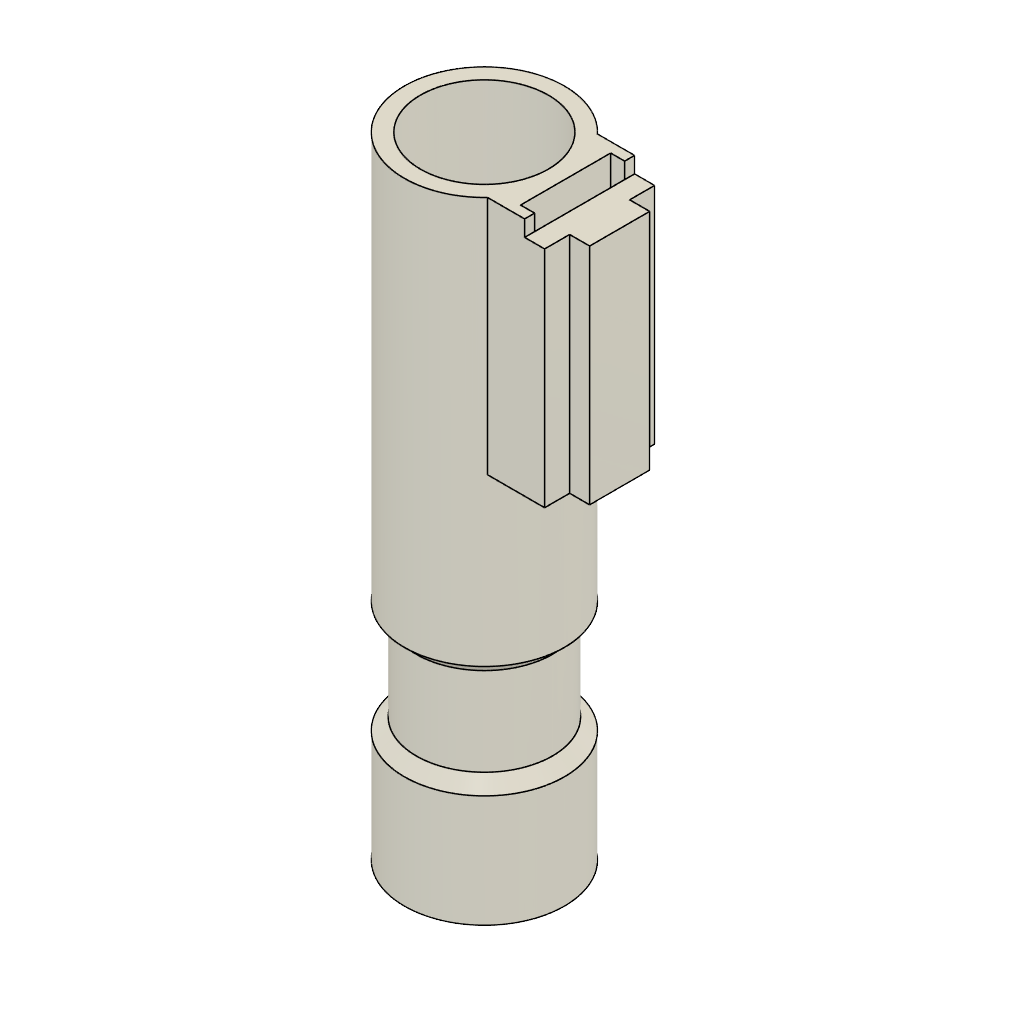
RealMainAssembly (Autodesk Fusion 360 archive; units mm, degrees)
design "upper_shaft"
part number: 2026-10-18-16-02-19-659
Autodesk Fusion 360 part; units mm, degrees
sketch "Sketch1" plane through (0, 0, 0) normal (0, 1, 0) x (1, 0, 0)
  circle A0 centre (0, 0) radius 4
  dimension "d1" = 8
  constraint coincident A0.centre origin
  measures "d1" diameter of A0
extrude "Extrude1" add sketch "Sketch1" along normal blind 5.9
sketch "Sketch2" plane through (0, 5.9, 0) normal (0, 1, 0) x (-1, 0, 0)
  circle A0 centre (0, 0) radius 4
  circle A1 centre (0, 0) radius 3.4
  dimension "d4" = 6.8
  constraint coincident A0.centre A1.centre
  measures "d4" diameter of A1
extrude "Extrude2" add sketch "Sketch2" along normal blind 5 contours A1
sketch "Sketch3" plane through (0, 10.9, 0) normal (0, 1, 0) x (-1, 0, 0)
  circle A0 centre (0, 0) radius 3.4
  circle A1 centre (0, 0) radius 4
  dimension "d7" = 8
  constraint coincident A0.centre A1.centre
  measures "d7" diameter of A1
extrude "Extrude3" add sketch "Sketch3" along normal blind 20.6 contours A0 | A1
chamfer "Chamfer1" distance 0.3 angle 45 2 edges at (3.1699, 5.9, 1.2295) (-3.7293, 5.9, 1.4465) tangent chain off
chamfer "Chamfer2" distance 0.3 angle 45 2 edges at (3.1699, 10.9, -1.2295) (3.7293, 10.9, -1.4465) tangent chain off
hole "Hole1" at (0, 31.5, 0) direction (0, -1, 0) diameter 6.4 end through all
sketch "Sketch4" plane through (0, 31.5, 0) normal (0, 1, 0) x (-1, 0, 0)
  circle A0 centre (0, 0) radius 3.2
  circle A1 centre (0, 0) radius 4
  line L0 (-2.9047, -2.75) -> (-6.76, -2.75)
  line L1 (-2.9047, 2.75) -> (-6.76, 2.75)
  line L2 (-6.76, -2.75) -> (-6.76, 2.75)
  dimension "d16" = 6.76
  dimension "d17" = 5.5
  constraint coincident A1 L0.start
  constraint horizontal L0
  constraint coincident A1 L1.start
  constraint horizontal L1
  constraint equal L0 L1
  measures "d16" horizontal distance of A0.centre L0.end
  measures "d17" distance of L0.start L1.start
extrude "Extrude4" add sketch "Sketch4" against normal blind 12 contours A1 L0 L1 L2
sketch "Sketch5" plane through (0, 31.5, 0) normal (0, 1, 0) x (-1, 0, 0)
  circle A0 centre (0, 0) radius 3.2
  arc A1 (-2.9047, -2.75) -> (-2.9047, 2.75) centre (0, 0) ccw
  line L0 (-2.9047, 2.75) -> (-6.76, 2.75)
  line L1 (-6.76, 2.75) -> (-6.76, -2.75)
  line L2 (-6.76, -2.75) -> (-2.9047, -2.75)
  line L3 (0, 0) -> (-6.76, 0) construction
  line L4 (-4.06, 0) -> (-4.06, -2.25)
  line L5 (-4.06, 0) -> (-4.06, 2.25)
  line L6 (-4.06, -2.25) -> (-4.76, -2.25)
  line L7 (-4.76, -2.25) -> (-4.76, 2.25)
  line L8 (-4.76, 2.25) -> (-4.06, 2.25)
  dimension "d30" = 2.25
  dimension "d31" = 2.25
  dimension "d32" = 0.7
  dimension "d33" = 4.5
  dimension "d34" = 4.06
  constraint coincident A0.centre A1.centre
  constraint midpoint L1 L3.end
  constraint coincident L3 L4.start
  constraint perpendicular L3 L4
  constraint perpendicular L3 L5
  constraint perpendicular L4 L6
  constraint perpendicular L6 L7
  measures "d30" distance of L4.start L4.end
  measures "d31" distance of L4.start L5.end
  measures "d32" distance of L4.end L6.end
  measures "d33" distance of L6.end L7.end
  measures "d34" distance of A0.centre L4
extrude "Extrude5" cut sketch "Sketch5" against normal blind 9 contours L4 L5 L6 L7 L8
sketch "Sketch6" plane through (0, 31.5, 0) normal (0, 1, 0) x (-1, 0, 0)
  line L0 (-4.76, 2.25) -> (-4.06, 2.25)
  line L1 (-4.06, 2.25) -> (-4.06, -2.25)
  line L2 (-4.06, -2.25) -> (-4.76, -2.25)
  line L3 (-4.76, -2.25) -> (-4.76, 2.25)
  circle A0 centre (0, 0) radius 3.2
  arc A1 (-2.9047, -2.75) -> (-2.9047, 2.75) centre (0, 0) ccw
  line L4 (-2.9047, 2.75) -> (-6.76, 2.75)
  line L5 (-6.76, 2.75) -> (-6.76, -2.75)
  line L6 (-6.76, -2.75) -> (-2.9047, -2.75)
  line L7 (-6.76, -2.75) -> (-5.76, -2.75)
  line L8 (-5.76, -2.75) -> (-5.76, -1.5)
  line L9 (-5.76, -1.5) -> (-6.76, -1.5)
  line L10 (-6.76, -1.5) -> (-6.76, -2.75)
  line L11 (-6.76, 2.75) -> (-5.76, 2.75)
  line L12 (-5.76, 2.75) -> (-5.76, 1.5)
  line L13 (-5.76, 1.5) -> (-6.76, 1.5)
  line L14 (-6.76, 1.5) -> (-6.76, 2.75)
  dimension "d37" = 3
  dimension "d39" = 5.76
  constraint horizontal L7
  constraint vertical L8
  constraint horizontal L9
  constraint vertical L10
  constraint coincident L5.end L6.start
  constraint horizontal L11
  constraint vertical L12
  constraint horizontal L13
  constraint vertical L14
  constraint coincident L4.end L5.start
  constraint equal L9 L13
  constraint equal L8 L12
  measures "d37" distance of L9.end L13.end
  measures "d39" distance of A0.centre L8
extrude "Extrude6" cut sketch "Sketch6" against normal blind 12 contours L5 L6 L7 L8 L9 L10 | L4 L5 L11 L12 L13 L14
sketch "Sketch7" plane through (6.76, 0, 0) normal (1, 0, 0) x (0, 0, -1)
  line L0 (-1.5, 31.5) -> (-1.5, 19.5)
  line L1 (-1.5, 19.5) -> (1.5, 19.5)
  line L2 (1.5, 19.5) -> (1.5, 31.5)
  line L3 (1.5, 31.5) -> (-1.5, 31.5)
  line L4 (-1.5, 31.5) -> (12.2094, 31.5)
  line L5 (12.2094, 31.5) -> (12.2094, 30.7)
  line L6 (12.2094, 30.7) -> (-1.5, 30.7)
  line L7 (-1.5, 30.7) -> (-1.5, 31.5)
  dimension "d42" = 0.8
  constraint horizontal L4
  constraint vertical L5
  constraint horizontal L6
  constraint vertical L7
  constraint coincident L0.start L3.end
  measures "d42" distance of L0.start L6.end
extrude "Extrude7" cut sketch "Sketch7" against normal blind 2 contours L2 L4 L5 L6
sketch "Sketch9" plane through (5.76, 0, 0) normal (1, 0, 0) x (0, 0, -1)
  line L0 (-1.5, 31.5) -> (-2.75, 31.5)
  line L1 (-2.75, 31.5) -> (-2.75, 19.5)
  line L2 (-2.75, 19.5) -> (-1.5, 19.5)
  line L3 (-1.5, 19.5) -> (-1.5, 31.5)
  line L4 (-2.75, 31.5) -> (-1.5, 31.5)
  line L5 (-1.5, 31.5) -> (-1.5, 30.7)
  line L6 (-1.5, 30.7) -> (-2.75, 30.7)
  line L7 (-2.75, 30.7) -> (-2.75, 31.5)
  dimension "d49" = 0.8
  constraint horizontal L4
  constraint vertical L5
  constraint horizontal L6
  constraint vertical L7
  constraint coincident L0.end L1.start
  measures "d49" distance of L0.end L6.end
extrude "Extrude9" cut sketch "Sketch9" against normal blind 1 contours L0 L1 L3 L4 L5 L6 L7
sketch "Sketch10" plane through (6.76, 0, 0) normal (1, 0, 0) x (0, 0, -1)
  line L0 (-1.5, 31.5) -> (-1.5, 19.5)
  line L1 (-1.5, 19.5) -> (1.5, 19.5)
  line L2 (1.5, 19.5) -> (1.5, 31.5)
  line L3 (1.5, 31.5) -> (-1.5, 31.5)
  line L4 (-1.5, 31.5) -> (1.5, 31.5)
  line L5 (1.5, 31.5) -> (1.5, 30.7)
  line L6 (1.5, 30.7) -> (-1.5, 30.7)
  line L7 (-1.5, 30.7) -> (-1.5, 31.5)
  dimension "d52" = 0.8
  constraint horizontal L4
  constraint vertical L5
  constraint horizontal L6
  constraint vertical L7
  constraint coincident L0.start L3.end
  measures "d52" distance of L0.start L6.end
extrude "Extrude10" cut sketch "Sketch10" against normal blind 2 contours L0 L2 L3 L4 L5 L6 L7
scale "Scale2" factor 3 about (4.76, 30.7, -2.75) bodies 1
equation "d5 = ( 45.9 mm - 5.9 mm ) - 35 mm"
equation "d8 = 66.50 mm - 45.9 mm"
equation "d30 = ( 4.5 / 2 ) * 1 mm"
equation "d31 = ( 4.5 / 2 ) * 1 mm"

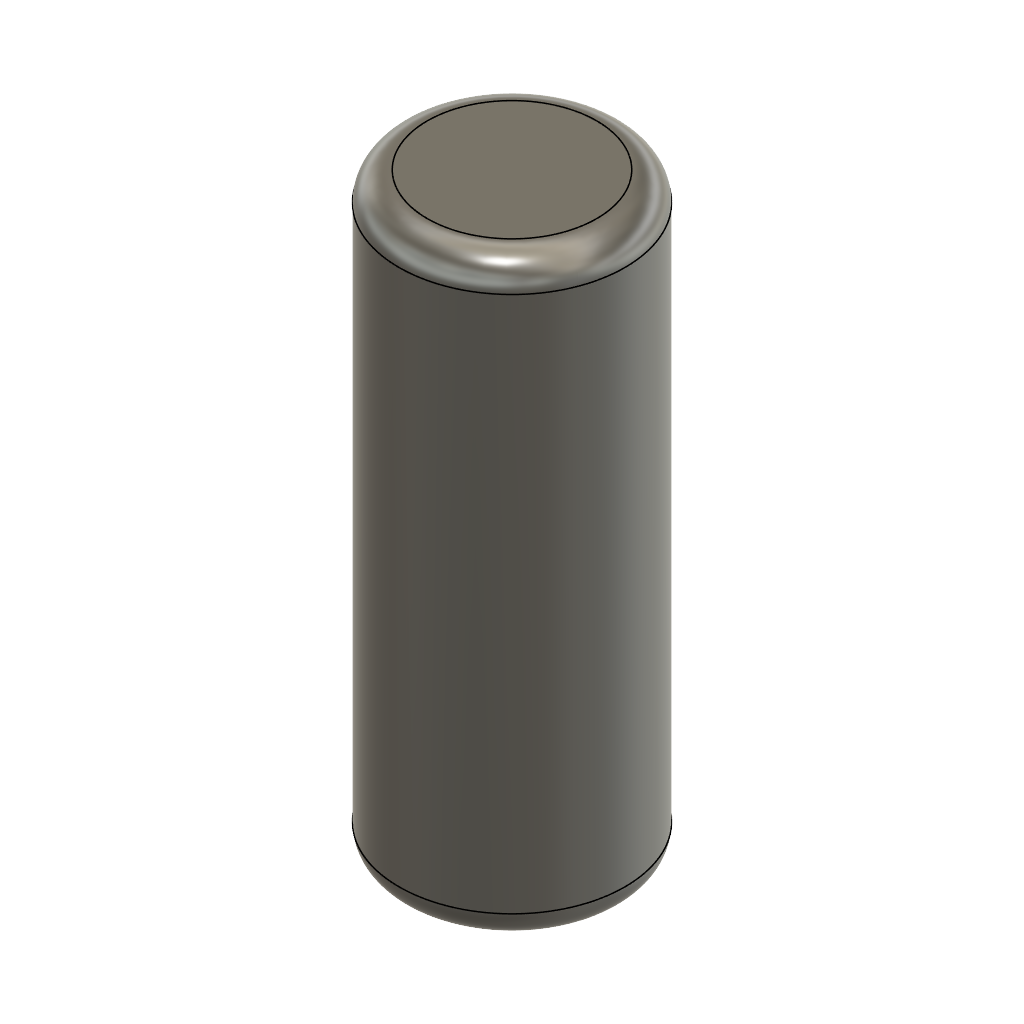
design "ERASER"
part number: 2026-10-18-16-44-17-259
Autodesk Fusion 360 part; units mm, degrees
sketch "Sketch1" plane through (0, 0, 0) normal (0, 1, 0) x (1, 0, 0)
  circle A0 centre (0, 0) radius 2
  dimension "d1" = 4
  constraint coincident A0.centre origin
  measures "d1" diameter of A0
extrude "Extrude1" add sketch "Sketch1" along normal blind 10.5
fillet "Fillet1" radius 0.5 2 edges at (-1.8647, 10.5, 0.7232) (-1.8647, 0, 0.7232)
scale "Scale1" factor 3 about (-2, 10, 0) bodies 1

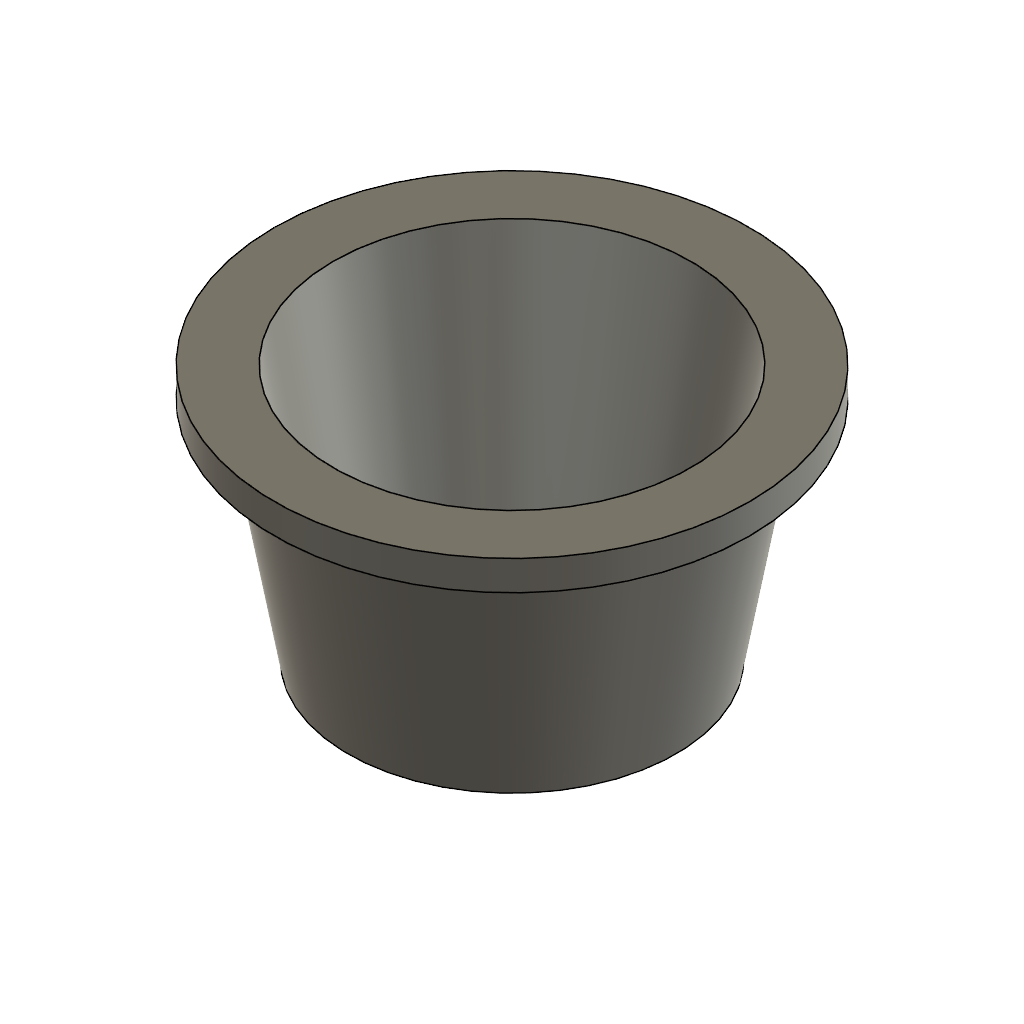
design "dispenser_ring"
part number: 2026-10-18-07-58-24-911
Autodesk Fusion 360 part; units mm, degrees
sketch "Sketch2" plane through (0, 0, 0) normal (0, 1, 0) x (1, 0, 0)
  circle A0 centre (0, 0) radius 1.38
  dimension "d10" = 2.76
  constraint coincident A0.centre origin
  measures "d10" diameter of A0
extrude "Extrude1" add sketch "Sketch2" along normal blind 1.9 draft 10
sketch "Sketch3" plane through (0, 1.9, 0) normal (0, 1, 0) x (-1, 0, 0)
  circle A0 centre (0, 0) radius 1.715
  circle A1 centre (0, 0) radius 2
  dimension "d13" = 4
  constraint coincident A0.centre A1.centre
  measures "d13" diameter of A1
extrude "Extrude2" add sketch "Sketch3" along normal blind 0.25 contours A0 | A1
shell "Shell1" thickness 0.25 removed faces 1 at (-0.637, 2.15, 0.1965)
sketch "Sketch4" plane through (0, 0.25, 0) normal (0, 1, 0) x (-1, 0, 0)
  circle A0 centre (0, 0) radius 1.1702
  circle A1 centre (0, 0) radius 0.95
  dimension "d17" = 1.9
  constraint coincident A0.centre A1.centre
  measures "d17" diameter of A1
sketch "Sketch5" plane through (0, 0, 0) normal (0, -1, 0) x (1, 0, 0)
  circle A0 centre (0, 0) radius 1.38
  circle A1 centre (0, 0) radius 0.8
  dimension "d18" = 1.6
  constraint coincident A0.centre A1.centre
  measures "d18" diameter of A1
loft "Loft1" cut profiles "Sketch4", "Sketch5" section 1 contours A1 section 2 contours A1
scale "Scale1" factor 3 about (2, 1.9, 0) bodies 1

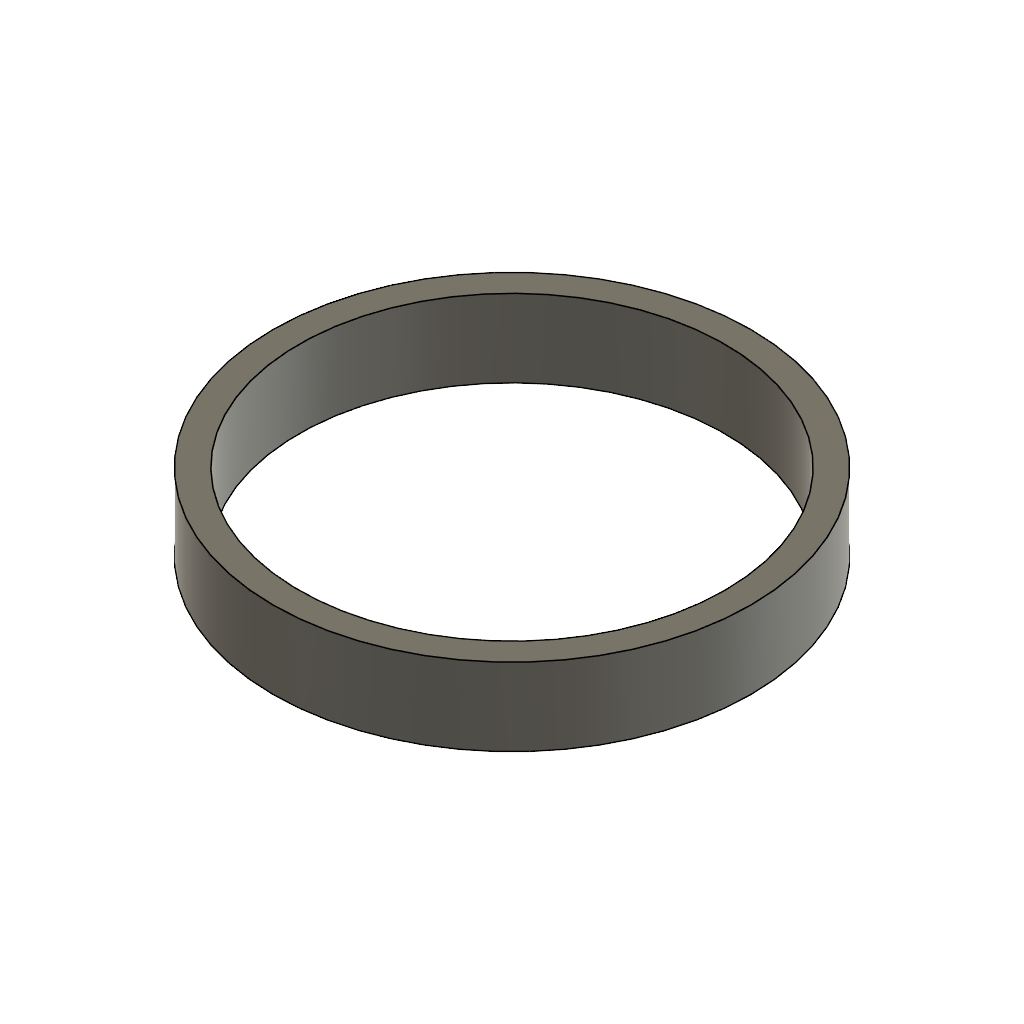
design "RING1"
part number: 2026-10-18-00-34-46-271
Autodesk Fusion 360 part; units mm, degrees
sketch "Sketch1" plane through (0, 0, 0) normal (0, 1, 0) x (1, 0, 0)
  circle A0 centre (0, 0) radius 4.2
  dimension "d1" = 8.4
  constraint coincident A0.centre origin
  measures "d1" diameter of A0
extrude "Extrude1" add sketch "Sketch1" along normal blind 1.5
sketch "Sketch2" plane through (0, 1.5, 0) normal (0, 1, 0) x (-1, 0, 0)
  circle A0 centre (0, 0) radius 4.2
  circle A1 centre (0, 0) radius 4.12
  dimension "d4" = 0.08
  constraint coincident A0.centre A1.centre
  measures "d4" distance of A0 A1
extrude "Extrude2" cut sketch "Sketch2" against normal blind 1.8 contours A1
scale "Scale1" factor 3 about (-4.2, 0, 0) bodies 1
move_face "OffsetFaces1" offset 1.26 1 faces at (20.9843, 3, 0.6281)

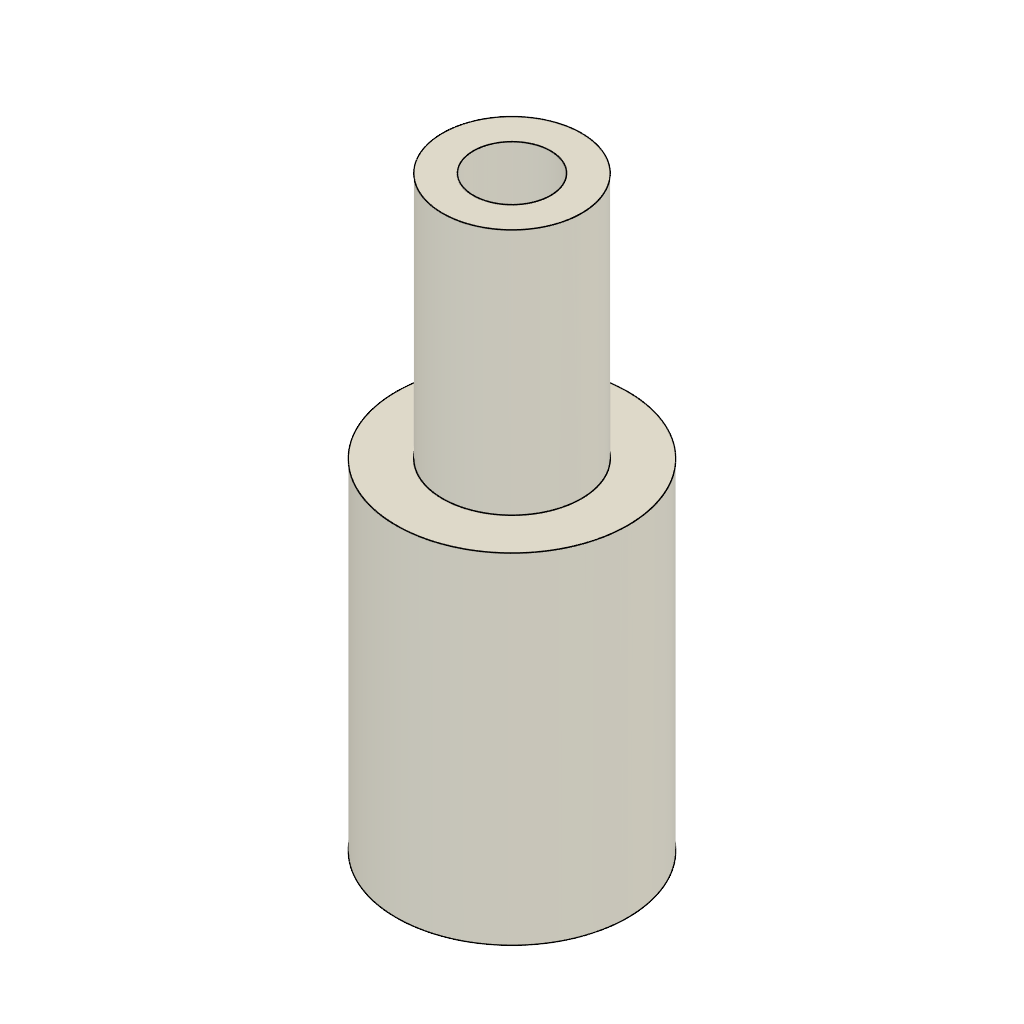
design "Coupling_1"
part number: 2026-10-18-00-37-06-966
Autodesk Fusion 360 part; units mm, degrees
sketch "Sketch1" plane through (0, 0, 0) normal (0, 0, 1) x (1, 0, 0)
  line L0 (0, 0) -> (1.5, 0)
  line L1 (1.5, 0) -> (1.5, 4.4)
  line L2 (1.5, 4.4) -> (0, 4.4)
  line L3 (0, 4.4) -> (0, 0)
  line L4 (0, 4.4) -> (0.9, 4.4)
  line L5 (0.9, 4.4) -> (0.9, 7.6)
  line L6 (0.9, 7.6) -> (0, 7.6)
  line L7 (0, 7.6) -> (0, 4.4)
  line L8 (0, 0) -> (0.65, 0)
  line L9 (0.65, 0) -> (0.65, 1.75)
  line L10 (0.65, 1.75) -> (0, 1.75)
  line L11 (0, 1.75) -> (0, 0)
  dimension "d1" = 1.5
  dimension "d2" = 4.4
  dimension "d3" = 0.9
  dimension "d4" = 7.6
  dimension "d5" = 0.65
  dimension "d6" = 1.75
  constraint horizontal L0
  constraint vertical L1
  constraint horizontal L2
  constraint vertical L3
  constraint coincident L0.start L3.end
  constraint horizontal L4
  constraint vertical L5
  constraint horizontal L6
  constraint vertical L7
  constraint horizontal L8
  constraint vertical L9
  constraint horizontal L10
  constraint vertical L11
  measures "d1" distance of L0.start L0.end
  measures "d2" distance of L0.start L2.end
  measures "d3" distance of L2.end L4.end
  measures "d4" distance of L0.start L6.end
  measures "d5" distance of L0.start L8.end
  measures "d6" distance of L0.start L10.end
revolve "Revolve1" add sketch "Sketch1" angle 360 about axis through (0, 1.75, 0) along (0, -1, 0) contours L0 L1 L2 L3 L4 L9 L10 | L2 L4 L5 L6 L7
sketch "Sketch2" plane through (0, 7.6, 0) normal (0, 1, 0) x (-1, 0, 0)
  circle A0 centre (0, 0) radius 0.9
  circle A1 centre (0, 0) radius 0.5
  dimension "d8" = 1
  constraint coincident A0.centre A1.centre
  measures "d8" diameter of A1
extrude "Extrude1" cut sketch "Sketch2" against normal blind 5.85 contours A1
scale "Scale1" factor 3 about (0.9, 4.4, 0) bodies 1
equation "d1 = ( 3 / 2 ) * 1 mm"
equation "d3 = ( 1.8 / 2 ) * 1 mm"
equation "d5 = ( 1.3 / 2 ) * 1 mm"

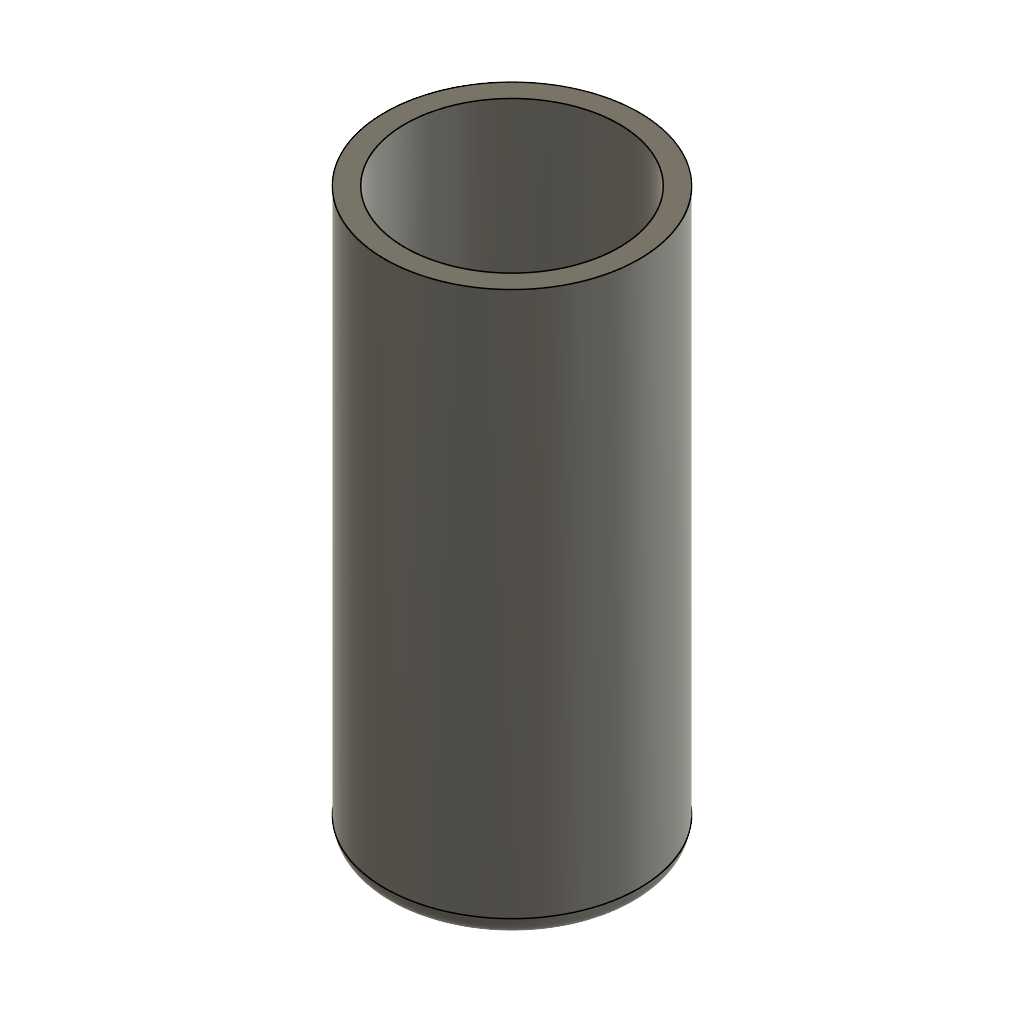
design "Eraser_cap"
part number: 2026-10-18-16-46-40-232
Autodesk Fusion 360 part; units mm, degrees
sketch "Sketch1" plane through (0, 0, 0) normal (0, 1, 0) x (1, 0, 0)
  circle A0 centre (0, 0) radius 3.15
  dimension "d1" = 6.3
  constraint coincident A0.centre origin
  measures "d1" diameter of A0
extrude "Extrude1" add sketch "Sketch1" along normal blind 14
hole "Hole1" at (0, 14, 0) direction (0, -1, 0) diameter 5.3 depth 13 tip angle 180
fillet "Fillet1" radius 0.5 1 edges at (-2.9368, 0, 1.1391)
scale "Scale1" factor 3 about (0, 1, 2.65) bodies 1

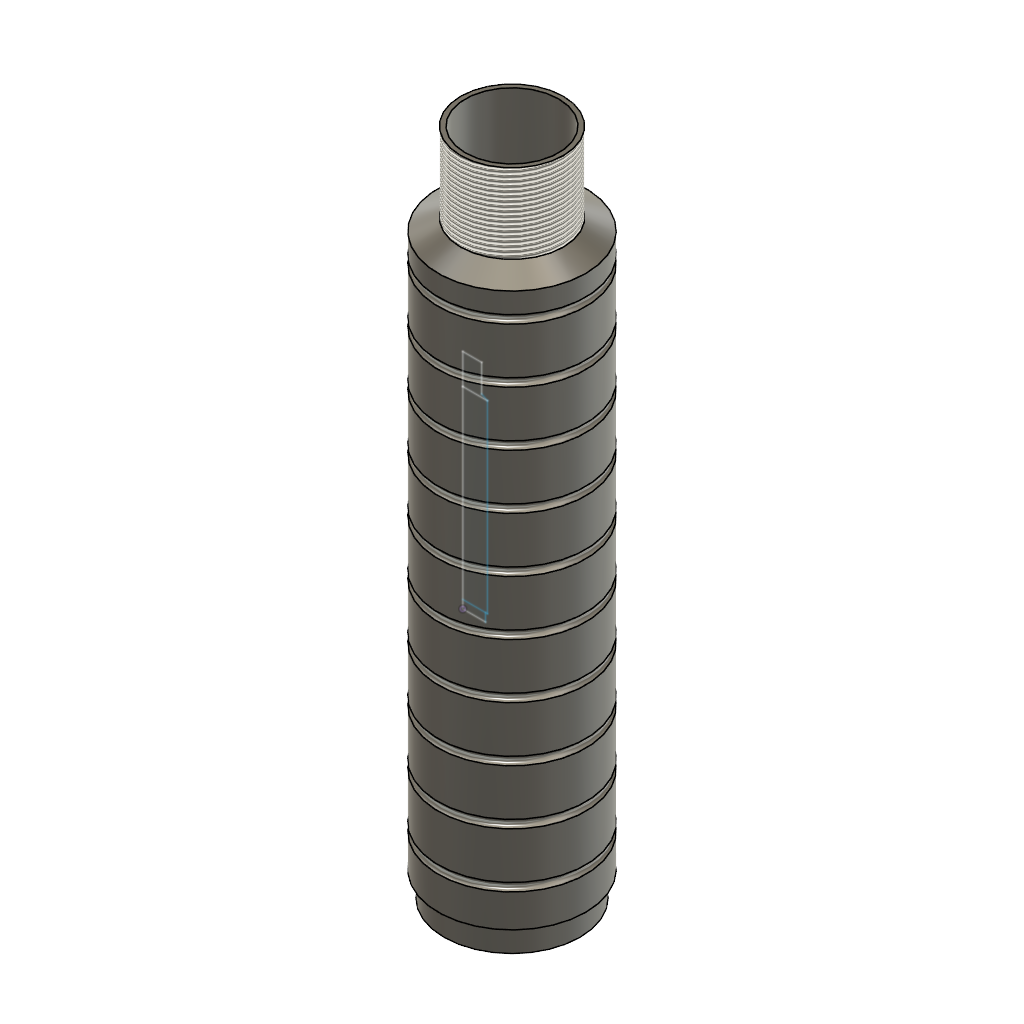
design "GRIP"
part number: 2026-10-18-08-55-25-582
Autodesk Fusion 360 part; units mm, degrees
sketch "Sketch4" plane through (0, 0, 0) normal (0, 0, 1) x (1, 0, 0)
  line L0 (0, 0) -> (4.15, 0)
  line L1 (4.5, 1.5) -> (4.5, 35.25)
  line L2 (4.5, 35.25) -> (0, 35.25)
  line L3 (0, 35.25) -> (0, 0)
  line L4 (0, 40.8) -> (3.45, 40.8)
  line L5 (3.45, 40.8) -> (3.45, 35.8)
  line L6 (3.45, 35.8) -> (4.5, 35.25)
  line L7 (0, 40.8) -> (0, 35.25)
  line L8 (4.5, 1.5) -> (0, 1.5)
  line L9 (4.15, 1.5) -> (4.15, 0)
  dimension "d10" = 35.25
  dimension "d12" = 3.45
  dimension "d13" = 0.55
  dimension "d39" = 0.35
  dimension "d41" = 40.8
  constraint horizontal L0
  constraint vertical L1
  constraint horizontal L2
  constraint vertical L3
  constraint coincident L0.start L3.end
  constraint horizontal L4
  constraint perpendicular L4 L5
  constraint perpendicular L2 L7
  constraint coincident L3 L8.end
  constraint perpendicular L3 L8
  constraint coincident L8 L9.start
  constraint perpendicular L0 L9
  measures "d10" distance of L0.start L2.end
  measures "d12" distance of L4.start L4.end
  measures "d13" vertical distance of L1.end L5.end
  measures "d39" distance of L1.start L9.start
  measures "d41" distance of L0.start L4.start
revolve "Revolve1" add sketch "Sketch4" angle 360 about axis through (0, 35.25, 0) along (0, -1, 0)
hole "Hole2" at (0, 40.8, 0) direction (0, -1, 0) diameter 5.7 end through all
sketch "Sketch6" plane through (0, 0, 0) normal (0, 0, 1) x (1, 0, 0)
  circle A0 centre (4.5, 33.75) radius 0.25
  point P0 (4.5, 35.25)
  dimension "d30" = 0.5
  dimension "d36" = 1.5
  measures "d30" diameter of A0
  measures "d36" distance of A0.centre P0
revolve "Revolve2" cut sketch "Sketch6" angle 360 about axis through (0, 1.5, 0) along (0, 1, 0)
pattern_linear "R-Pattern1" count 10 spacing 3.333 along (0, -1, 0) of 1 faces at (4.482, 33.9997, 0.2237)
thread "Thread2" "ANSI Unified Screw Threads 0.25 1/4-32 UNEF 1/4-32 UNEF 3A" major diameter 6.2738 minor diameter 5.4051 pitch 0.7937 angle 60 resizes the face on face at (3.4457, 39.1333, -0.172)
scale "Scale1" factor 3 about (-4.5, 20.668, 0) bodies 1
equation "d12 = ( 6.9 / 2 ) * 1 mm"
equation "d39 = 0.27 mm + 0.08 mm"

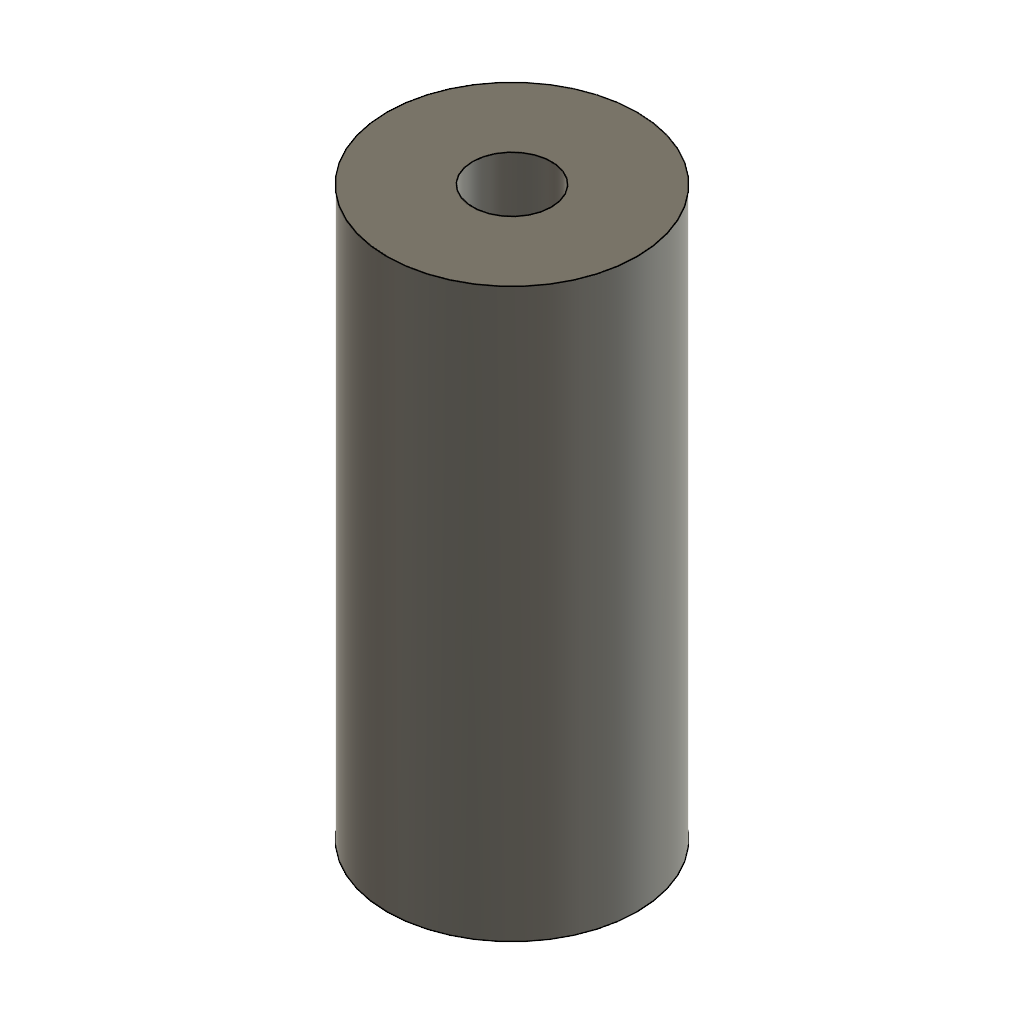
design "Lead_Guide"
part number: 2026-10-17-23-59-08-145
Autodesk Fusion 360 part; units mm, degrees
sketch "Sketch1" plane through (0, 0, 0) normal (0, 1, 0) x (1, 0, 0)
  circle A0 centre (0, 0) radius 0.46
  dimension "d1" = 0.92
  constraint coincident A0.centre origin
  measures "d1" diameter of A0
extrude "Extrude1" add sketch "Sketch1" along normal blind 3.6
sketch "Sketch2" plane through (0, 3.6, 0) normal (0, 1, 0) x (-1, 0, 0)
  circle A0 centre (0, 0) radius 0.46
  circle A1 centre (0, 0) radius 0.25
  dimension "d4" = 0.5
  constraint coincident A0.centre A1.centre
  measures "d4" diameter of A1
extrude "Extrude2" cut sketch "Sketch2" against normal blind 4.4 contours A1
scale "Scale1" factor 3 about (-0.46, 3.6, 0) bodies 1
move_face "OffsetFaces1" offset 1 1 faces at (2.2983, 0, 0.0688)

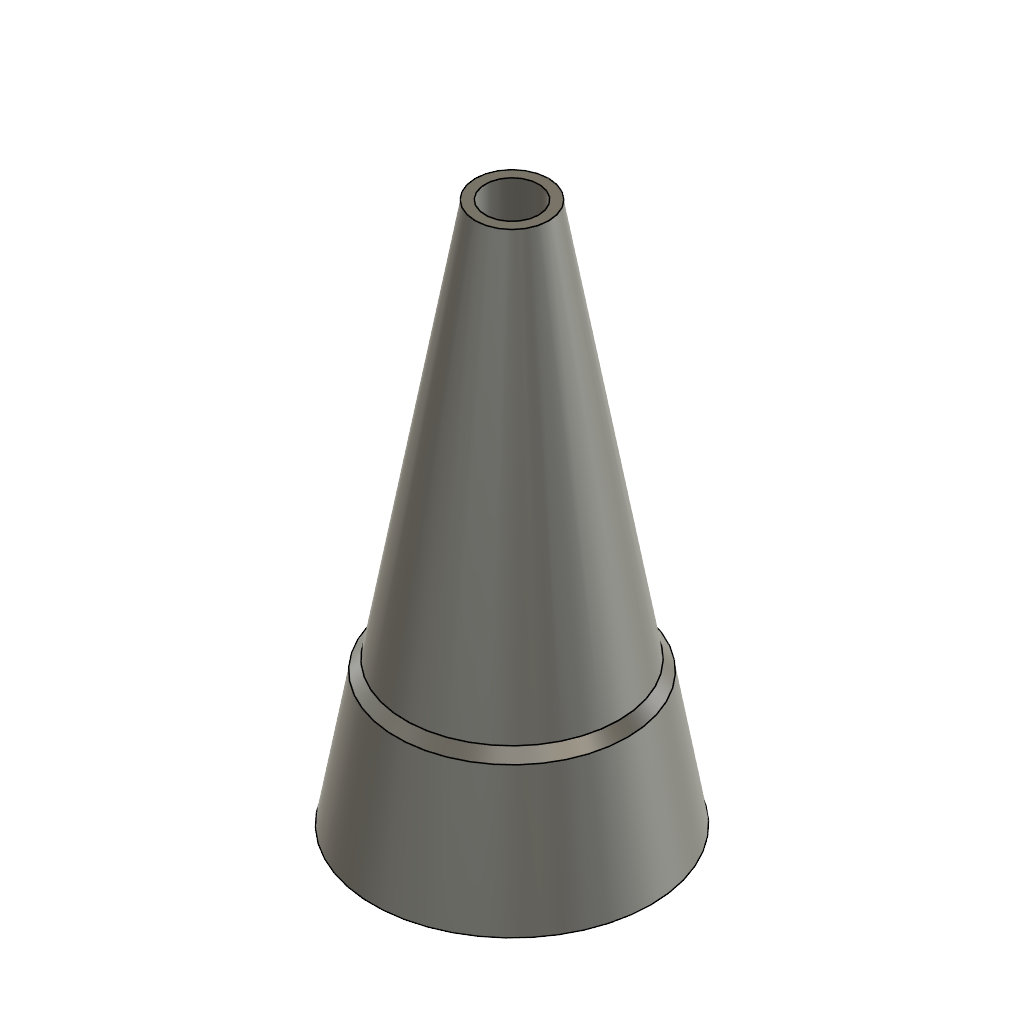
design "main_cone"
part number: 2026-10-18-00-08-41-447
Autodesk Fusion 360 part; units mm, degrees
sketch "Sketch1" plane through (0, 0, 0) normal (0, 0, 1) x (1, 0, 0)
  line L0 (0, 0) -> (4.165, 0)
  line L1 (0, 0) -> (0, 16.2)
  line L2 (3.46, 3.99) -> (4.165, 0)
  line L3 (3.2, 4.3) -> (3.46, 3.99)
  line L4 (0, 16.2) -> (1.1, 16.2)
  line L5 (1.1, 16.2) -> (3.2, 4.3)
  line L6 (0, 0) -> (2.905, 0)
  line L7 (2.905, 0) -> (2.905, 5.51)
  line L8 (2.905, 5.51) -> (0, 5.51)
  line L9 (0, 5.51) -> (0, 0)
  line L10 (0, 5.51) -> (1.75, 5.51)
  line L11 (1.75, 5.51) -> (1.75, 8)
  line L12 (1.75, 8) -> (0, 8)
  line L13 (0, 8) -> (0, 5.51)
  line L14 (0, 9.9) -> (1.4, 9.9)
  line L15 (1.4, 9.9) -> (1.75, 8)
  line L16 (0, 16.2) -> (0.72, 16.2)
  line L17 (0, 14.9) -> (0, 16.2)
  dimension "d1" = 4.165
  dimension "d2" = 3.99
  dimension "d5" = 4.3
  dimension "d10" = 16.2
  dimension "d13" = 1.1
  dimension "d14" = 2.905
  dimension "d15" = 5.51
  dimension "d16" = 8
  dimension "d17" = 1.75
  dimension "d18" = 9.9
  dimension "d19" = 1.4
  constraint coincident L0.start L1.start
  constraint horizontal L0
  constraint perpendicular L0 L1
  constraint perpendicular L1 L4
  constraint horizontal L6
  constraint vertical L7
  constraint horizontal L8
  constraint vertical L9
  constraint horizontal L10
  constraint vertical L11
  constraint horizontal L12
  constraint vertical L13
  constraint coincident L1 L14.start
  constraint perpendicular L1 L14
  constraint horizontal L16
  constraint vertical L17
  measures "d1" distance of L0.start L0.end
  measures "d2" vertical distance of L0.end L2.start
  measures "d5" vertical distance of L0.end L3.start
  measures "d10" distance of L0.start L1.end
  measures "d13" distance of L1.end L4.end
  measures "d14" distance of L0.start L6.end
  measures "d15" distance of L0.start L8.end
  measures "d16" distance of L0.start L12.end
  measures "d17" distance of L11.end L12.end
  measures "d18" distance of L0.start L14.start
  measures "d19" distance of L14.start L14.end
revolve "Revolve1" add sketch "Sketch1" angle 360 about axis through (0, 0, 0) along (0, 1, 0) contours L0 L1 L2 L3 L4 L5 L7 L8 L11 L14 L15 L16 L17
sketch "Sketch2" plane through (0, 16.2, 0) normal (0, 1, 0) x (-1, 0, 0)
  circle A0 centre (0, 0) radius 1.1
  circle A1 centre (0, 0) radius 0.8
  dimension "d21" = 1.6
  constraint coincident A0.centre A1.centre
  measures "d21" diameter of A1
extrude "Extrude1" cut sketch "Sketch2" against normal blind 6.3 contours A1
scale "Scale1" factor 3 about (2.905, 5.51, 0) bodies 1
equation "d1 = ( 8.33 / 2 ) * 1 mm"
equation "d13 = ( 2.2 / 2 ) * 1 mm"
equation "d14 = ( 5.81 / 2 ) * 1 mm"
equation "d17 = ( 3.50 / 2 ) * 1 mm"
equation "d19 = ( 2.8 / 2 ) * 1 mm"

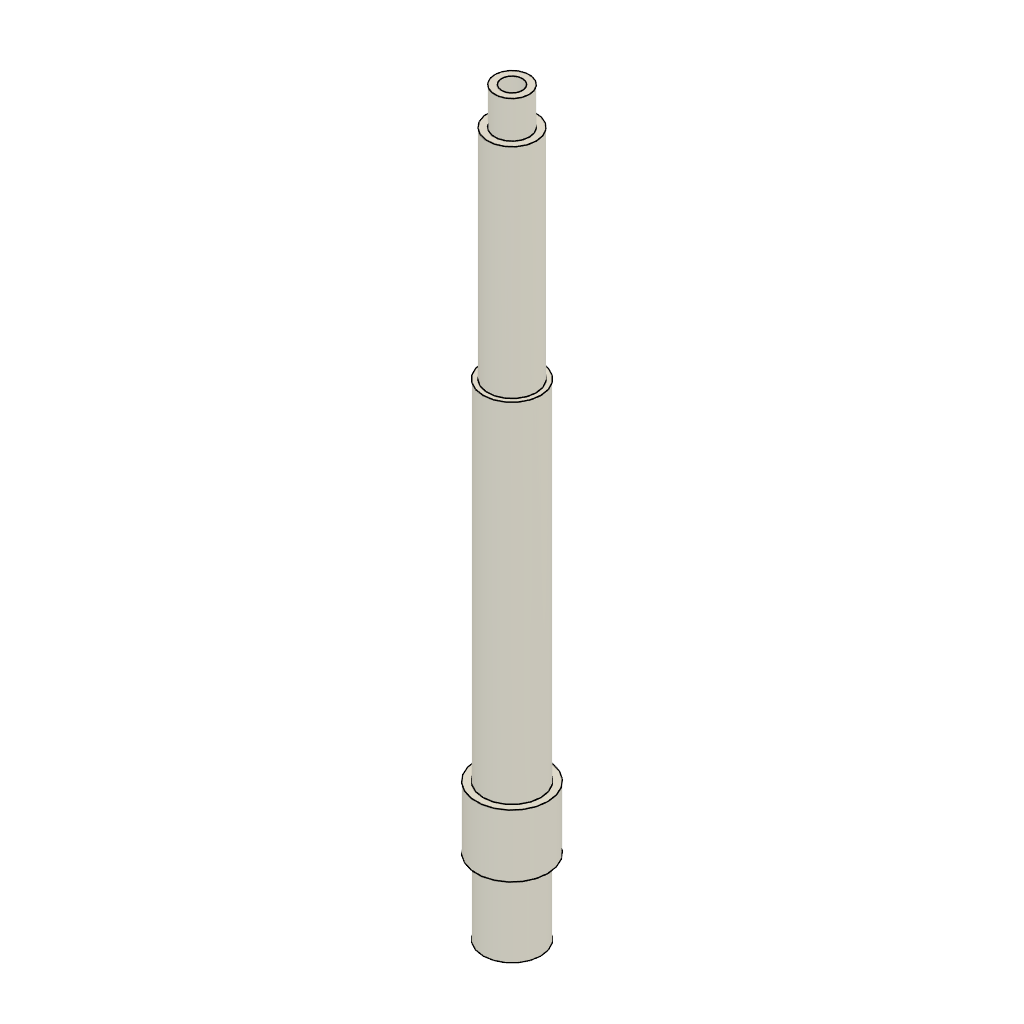
design "Shaft"
part number: 2026-10-18-08-16-24-793
Autodesk Fusion 360 part; units mm, degrees
sketch "Sketch1" plane through (0, 0, 0) normal (0, 0, 1) x (1, 0, 0)
  line L0 (0, 0) -> (0, 64.2)
  line L1 (0, 64.2) -> (1.5, 64.2)
  line L2 (1.5, 64.2) -> (1.5, 61)
  line L3 (1.5, 61) -> (2.1, 61)
  line L4 (2.1, 61) -> (2.1, 42.1)
  line L5 (2.1, 42.1) -> (2.5, 42.1)
  line L6 (2.5, 42.1) -> (2.5, 14.9314)
  line L7 (3.1, 8.8) -> (3.1, 6.5)
  line L8 (3.1, 6.5) -> (2.5, 6.5)
  line L9 (2.5, 6.5) -> (2.5, 0)
  line L10 (2.5, 0) -> (0, 0)
  line L11 (2.5, 11.9) -> (3.1, 11.9)
  line L12 (3.1, 11.9) -> (3.1, 8.8)
  line L13 (2.5, 14.9314) -> (2.5, 11.9)
  dimension "d1" = 64.2
  dimension "d3" = 6.5
  dimension "d5" = 42.1
  dimension "d6" = 61
  dimension "d7" = 1.5
  dimension "d8" = 2.1
  dimension "d9" = 2.5
  dimension "d10" = 2.5
  dimension "d13" = 3.1
  dimension "d14" = 90
  dimension "d15" = 11.9
  dimension "d30" = 3.1
  constraint vertical L0
  constraint coincident L0.start L10.end
  constraint perpendicular L0 L1
  constraint perpendicular L1 L2
  constraint perpendicular L2 L3
  constraint perpendicular L3 L4
  constraint perpendicular L4 L5
  constraint perpendicular L5 L6
  constraint perpendicular L5 L7
  constraint perpendicular L7 L8
  constraint perpendicular L8 L9
  constraint perpendicular L0 L10
  constraint perpendicular L6 L11
  constraint perpendicular L11 L13
  measures "d1" distance of L0.start L0.end
  measures "d3" distance of L8.end L9.end
  measures "d5" vertical distance of L5.end L9.end
  measures "d6" vertical distance of L3.end L9.end
  measures "d7" distance of L0.end L1.end
  measures "d8" distance of L0 L4
  measures "d9" distance of L0 L6
  measures "d10" distance of L0 L9
  measures "d13" vertical distance of L7.start L11.start
  measures "d14" angle of L11 L12
  measures "d15" vertical distance of L9.end L11.end
  measures "d30" distance of L0 L11.end
revolve "Revolve1" add sketch "Sketch1" angle 360 about axis through (0, 0, 0) along (0, 1, 0)
hole "Hole2" at (0, 0, 0) direction (0, 1, 0) diameter 1.8 end through all counterbore diameter 3.8 counterbore depth 59
sketch "Sketch2" plane through (0, 0, 0) normal (0, -1, 0) x (1, 0, 0)
  circle A0 centre (0, 0) radius 1.9
  circle A1 centre (0, 0) radius 2.5
  circle A2 centre (0, 0) radius 2.075
  dimension "d26" = 4.15
  constraint coincident A0.centre A1.centre
  measures "d26" diameter of A2
extrude "Extrude1" cut sketch "Sketch2" against normal blind 6.9 contours A2
chamfer "Chamfer1" distance 0.175 angle 45 1 edges at (-0.6871, 6.9, 1.7714) tangent chain off
scale "Scale2" factor 3 about (2.5, 11.9, 0) bodies 1
equation "d1 = 99.2 mm - 35 mm"
equation "d5 = 77.1 mm - 35 mm"
equation "d6 = 96 mm - 35 mm"
equation "d7 = ( 3 / 2 ) * 1 mm"
equation "d8 = ( 4.2 / 2 ) * 1 mm"
equation "d9 = ( 5 / 2 ) * 1 mm"
equation "d10 = ( 5 / 2 ) * 1 mm"
equation "d24 = 94 mm - 35 mm"
equation "d30 = ( 6.2 / 2 ) * 1 mm"

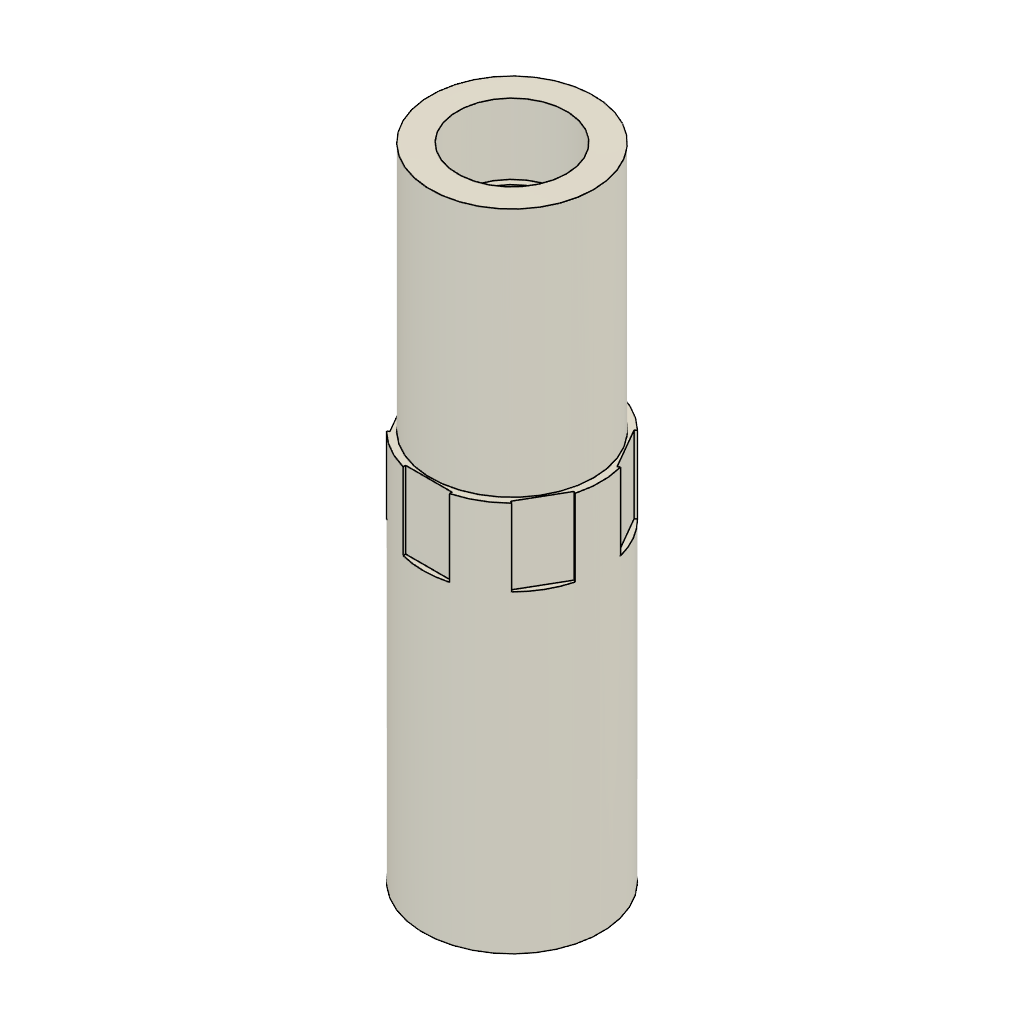
design "ShaftDispenser"
part number: 2026-10-18-07-35-43-858
Autodesk Fusion 360 part; units mm, degrees
sketch "Sketch1" plane through (0, 0, 0) normal (0, 1, 0) x (1, 0, 0)
  circle A0 centre (0, 0) radius 2.775
  dimension "d1" = 5.55
  constraint coincident A0.centre origin
  measures "d1" diameter of A0
extrude "Extrude1" add sketch "Sketch1" along normal blind 12.2
sketch "Sketch2" plane through (0, 12.2, 0) normal (0, 1, 0) x (-1, 0, 0)
  circle A0 centre (0, 0) radius 2.775
  circle A1 centre (0, 0) radius 2.55
  dimension "d4" = 5.1
  constraint coincident A0.centre A1.centre
  measures "d4" diameter of A1
extrude "Extrude2" add sketch "Sketch2" along normal blind 7.8 contours A1
hole "Hole1" at (0, 0, 0) direction (0, 1, 0) diameter 3 depth 20 tip angle 180 counterbore diameter 4.2 counterbore depth 14
sketch "Sketch3" plane through (0, 20, 0) normal (0, 1, 0) x (-1, 0, 0)
  circle A0 centre (0, 0) radius 1.5
  circle A1 centre (0, 0) radius 2.55
  circle A2 centre (0, 0) radius 1.7
  dimension "d12" = 3.4
  constraint coincident A0.centre A1.centre
  measures "d12" diameter of A2
extrude "Extrude3" cut sketch "Sketch3" against normal blind 2.2 contours A0 | A2
sketch "Sketch4" plane through (0, 12.2, 0) normal (0, 1, 0) x (-1, 0, 0)
  circle A0 centre (0, 0) radius 2.55
  circle A1 centre (0, 0) radius 2.775
  line L0 (-0.725, 2.6786) -> (-0.725, 2.6)
  line L1 (-0.725, 2.6) -> (0.725, 2.6)
  line L2 (0.725, 2.6) -> (0.725, 2.6786)
  dimension "d15" = 1.45
  dimension "d16" = 2.6
  constraint coincident A1 L0.start
  constraint vertical L0
  constraint perpendicular L0 L1
  constraint coincident A1 L2.end
  constraint perpendicular L1 L2
  constraint equal L0 L2
  measures "d15" distance of L0.end L1.end
  measures "d16" distance of A0.centre L1
extrude "Extrude4" cut sketch "Sketch4" against normal blind 2.4 contours A1 L0 L1 L2 picked at (0, 2.6583)
pattern_circular "C-Pattern1" count 6 over 360 about axis through (0, 1.75, 0) along (0, 1, 0) of "Extrude4"
scale "Scale1" factor 3 about (0, 14, -2.1) bodies 1
equation "d5 = 20 mm - 12.2 mm"
equation "d10 = 20 mm - 6 mm"

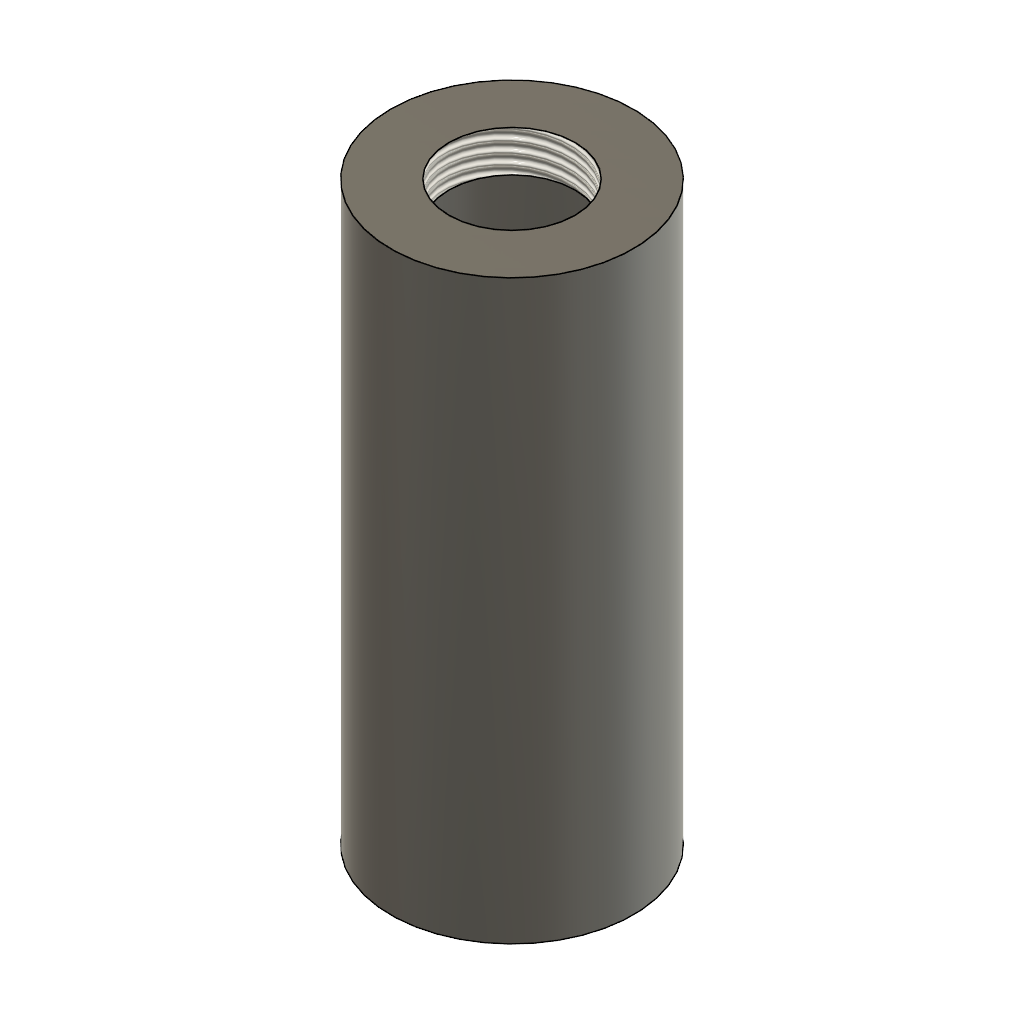
design "Sleeve"
part number: 2026-10-18-09-11-50-654
Autodesk Fusion 360 part; units mm, degrees
sketch "Sketch1" plane through (0, 0, 0) normal (0, 1, 0) x (1, 0, 0)
  circle A0 centre (0, 0) radius 4.25
  dimension "d1" = 8.5
  constraint coincident A0.centre origin
  measures "d1" diameter of A0
extrude "Extrude1" add sketch "Sketch1" along normal blind 23.4
sketch "Sketch2" plane through (0, 23.4, 0) normal (0, 1, 0) x (-1, 0, 0)
  circle A0 centre (0, 0) radius 4.25
  circle A1 centre (0, 0) radius 4.04
  dimension "d7" = 0.21
  constraint coincident A0.centre A1.centre
  measures "d7" distance of A0 A1
extrude "Extrude2" cut sketch "Sketch2" against normal blind 60 contours A1
thread "Thread1" "ANSI Unified Screw Threads 0.25 1/4-20 UNC 1/4-20 UNC 3B" major diameter 6.35 minor diameter 5.1156 pitch 1.27 angle 60 resizes the face on face at (-4.0199, 15.6, -0.4023) from (0, 23.4, 0) to (0, 18.4, 0)
scale "Scale1" factor 3 about (-4.25, 23.4, 0) bodies 1
sketch "Sketch3" plane through (0, -46.8, 0) normal (0, -1, 0) x (1, 0, 0)
  circle A0 centre (8.5, 0) radius 7.6733
  circle A1 centre (8.5, 0) radius 12.75
  circle A2 centre (8.5, 0) radius 12.12
  dimension "d13" = 0.63
  constraint concentric A0 A2
  measures "d13" distance of A1 A2
extrude "Extrude3" cut sketch "Sketch3" against normal blind 65.2 contours A2
move_face "OffsetFaces1" offset 2 1 faces at (21.1866, -23.4, 1.2695)
equation "d2 = 58.4 mm - 35 mm"
equation "d13 = ( 0.21 * 3 ) * 1 mm"

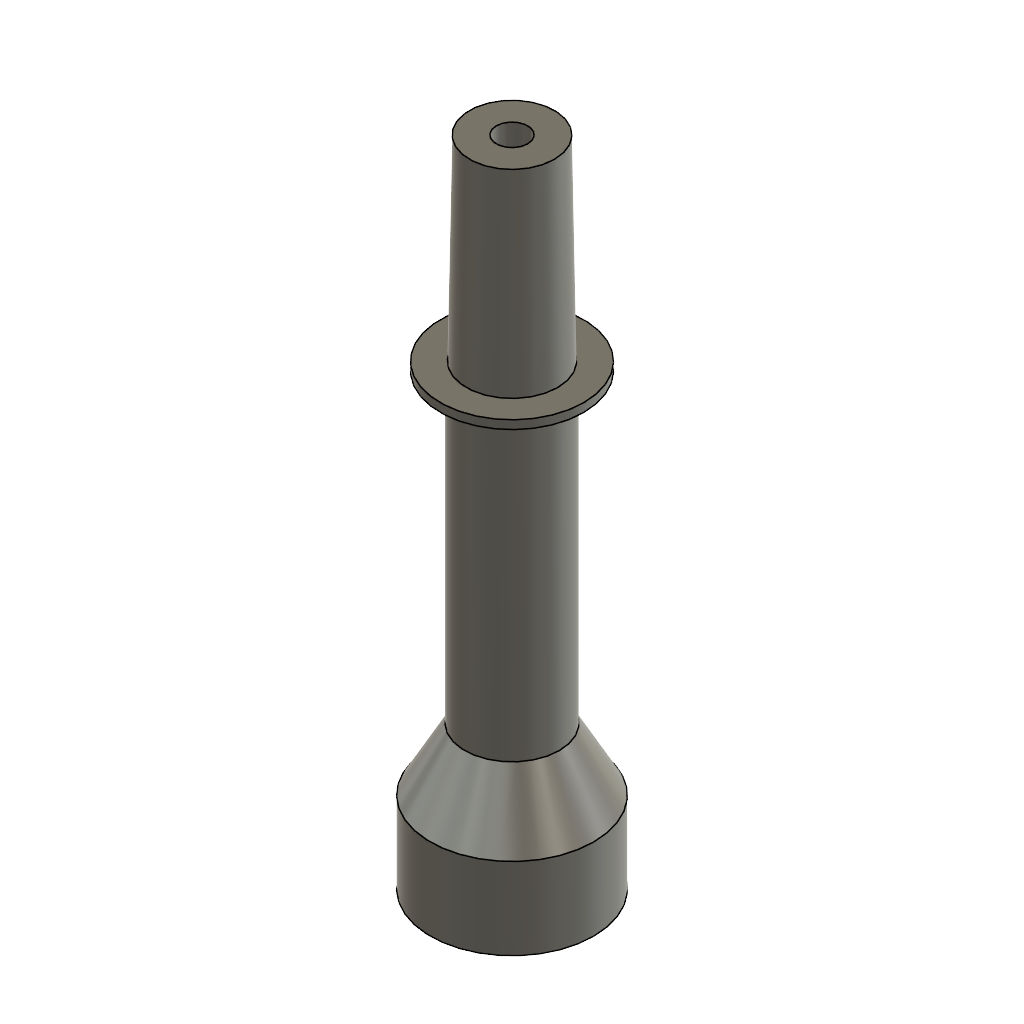
design "Dispenser"
part number: 2026-10-18-00-42-03-667
Autodesk Fusion 360 part; units mm, degrees
sketch "Sketch1" plane through (0, 0, 0) normal (0, 0, 1) x (1, 0, 0)
  line L0 (0, 0) -> (1.25, 0)
  line L1 (1.25, 0) -> (1.25, 1.25)
  line L2 (0.725, 2.2) -> (0.725, 6.62)
  line L3 (0, 0) -> (0, 10)
  line L4 (0.725, 2.2) -> (1.25, 1.25)
  line L5 (0, 6.87) -> (1.1, 6.87)
  line L6 (0.725, 6.62) -> (1.1, 6.87)
  line L7 (0, 7) -> (1.1, 7)
  line L8 (1.1, 7) -> (1.1, 6.87)
  line L9 (0, 10) -> (0.65, 10)
  line L10 (0, 7) -> (0.7, 7)
  line L11 (0.65, 10) -> (0.7, 7)
  dimension "d1" = 1.25
  dimension "d2" = 1.25
  dimension "d3" = 2.2
  dimension "d4" = 10
  dimension "d5" = 0.725
  dimension "d6" = 4.42
  dimension "d7" = 1.1
  dimension "d8" = 0.25
  dimension "d9" = 0.13
  dimension "d11" = 0.65
  dimension "d12" = 0.7
  constraint coincident L0.start L3.start
  constraint horizontal L0
  constraint perpendicular L0 L1
  constraint vertical L2
  constraint perpendicular L0 L3
  constraint coincident L3 L5.start
  constraint perpendicular L3 L5
  constraint coincident L3 L7.start
  constraint perpendicular L3 L7
  constraint perpendicular L5 L8
  constraint perpendicular L3 L9
  constraint perpendicular L3 L10
  measures "d1" distance of L0.start L0.end
  measures "d2" distance of L0.end L1.end
  measures "d3" vertical distance of L0.end L2.start
  measures "d4" distance of L0.start L3.end
  measures "d5" distance of L2 L3
  measures "d6" distance of L2.start L2.end
  measures "d7" distance of L5.start L5.end
  measures "d8" distance of L2.end L5
  measures "d9" distance of L5.end L7.end
  measures "d11" distance of L3.end L9.end
  measures "d12" distance of L7.start L10.end
revolve "Revolve1" add sketch "Sketch1" angle 360 about axis through (0, 0, 0) along (0, 1, 0)
sketch "Sketch2" plane through (0, 10, 0) normal (0, 1, 0) x (-1, 0, 0)
  circle A0 centre (0, 0) radius 0.65
  circle A1 centre (0, 0) radius 0.24
  dimension "d14" = 0.48
  constraint coincident A0.centre A1.centre
  measures "d14" diameter of A1
extrude "Extrude1" cut sketch "Sketch2" against normal blind 11.9 contours A1
scale "Scale1" factor 3 about (1.1, 6.87, 0) bodies 1
equation "d1 = ( 2.5 / 2 ) * 1 mm"
equation "d5 = ( 1.45 / 2 ) * 1 mm"
equation "d7 = ( 2.2 / 2 ) * 1 mm"
equation "d11 = ( 1.3 / 2 ) * 1 mm"

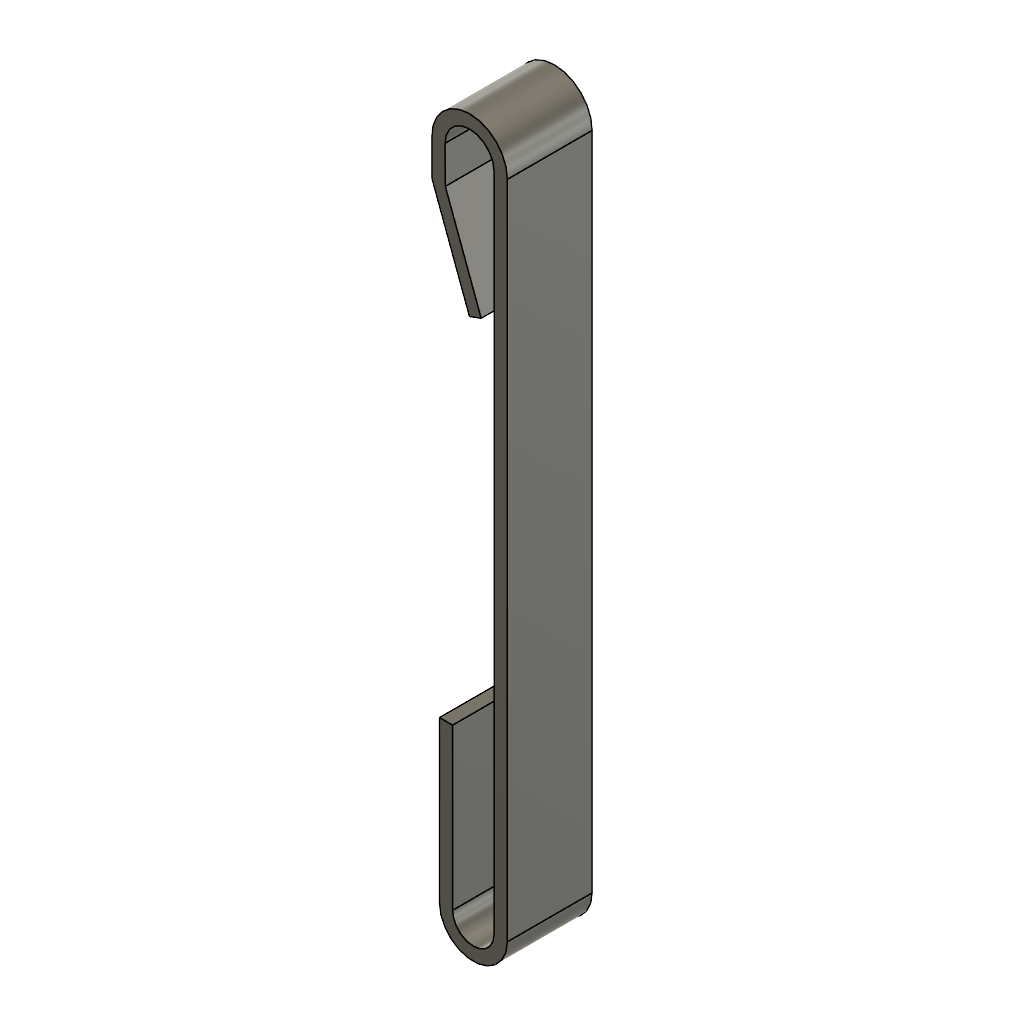
design "Clip"
part number: 2026-10-18-15-30-59-066
Autodesk Fusion 360 part; units mm, degrees
sketch "Sketch1" plane through (0, 0, 0) normal (0, 0, 1) x (1, 0, 0)
  line L0 (-1.8, 0) -> (-1.8, 8.5)
  line L1 (-1.8, 8.5) -> (-1.1, 8.5)
  line L2 (-1.1, 8.5) -> (-1.1, 0)
  line L3 (-1.1, 0) -> (-1.8, 0)
  line L4 (1.8, 0) -> (1.1, 0)
  line L5 (1.1, 0) -> (1.1, 35.04)
  line L6 (1.1, 35.04) -> (1.8, 35.04)
  line L7 (1.8, 35.04) -> (1.8, 0)
  line L8 (-2.1997, 35.0579) -> (-2.1967, 33.0479)
  line L9 (-2.1967, 33.0479) -> (-1.4855, 33.049)
  line L10 (-1.4855, 33.049) -> (-1.4999, 35.0178)
  line L11 (-2.1967, 33.0479) -> (-0.208, 27.7061)
  line L12 (-0.208, 27.7061) -> (0.4169, 27.9387)
  line L13 (0.4169, 27.9387) -> (-1.4855, 33.049)
  arc A0 (1.8, 35.0116) -> (-2.1996, 34.9907) centre (-0.1999, 35.0273) ccw
  arc A1 (1.1, 35.0146) -> (-1.4999, 35.0178) centre (-0.1999, 35.0273) ccw
  arc A2 (-1.8, 0) -> (1.8, 0.0004) centre (0, 0) ccw
  arc A3 (-1.1, 0) -> (1.1, 0.0005) centre (0, 0) ccw
  dimension "d6" = 1.8
  dimension "d7" = 0.7
  dimension "d9" = 35.04
  dimension "d10" = 0.7
  dimension "d11" = 8.5
  dimension "d12" = 1.3
  dimension "d15" = 2.01
  dimension "d17" = 90
  dimension "d18" = 5.7
  dimension "d19" = 160
  constraint coincident A2.centre A3.centre
  constraint vertical L0
  constraint perpendicular L0 L1
  constraint perpendicular L1 L2
  constraint perpendicular L3 A2
  constraint coincident L4.start A2
  constraint perpendicular L0 L4
  constraint perpendicular L4 L5
  constraint perpendicular L5 L6
  constraint coincident L5.end A1
  constraint coincident L8.start A0
  constraint perpendicular L8 L9
  constraint tangent L10 A1
  constraint perpendicular L11 L12
  constraint concentric A0 A1
  constraint coincident L5 A1.start
  constraint concentric A2 A3
  constraint coincident L5 A3.end
  constraint coincident L7 A2.end
  constraint coincident L7 A0.start
  constraint coincident L8 A0.end
  measures "d6" radius of A2
  measures "d7" distance of L0.end L1.end
  measures "d9" distance of L4.end L5.end
  measures "d10" distance of L5.end L6.end
  measures "d11" distance of L0.start L0.end
  measures "d12" radius of A1
  measures "d15" distance of L8.start L8.end
  measures "d17" angle of L12 L13
  measures "d18" distance of L8.end L11.end
  measures "d19" angle of L10 L13
extrude "Extrude1" add sketch "Sketch1" along normal blind 4.5
move_body "Move1" bodies 1 to x (1, 0, 0) y (0, 1, 0) z (0, 0, 1) at (0, 1.8, 0)
scale "Scale1" factor 3 about (1.8, 36.8116, 0) bodies 1
equation "d15 = 3.31 mm - 1.3 mm"
equation "d19 = 180 deg - 20 deg"
